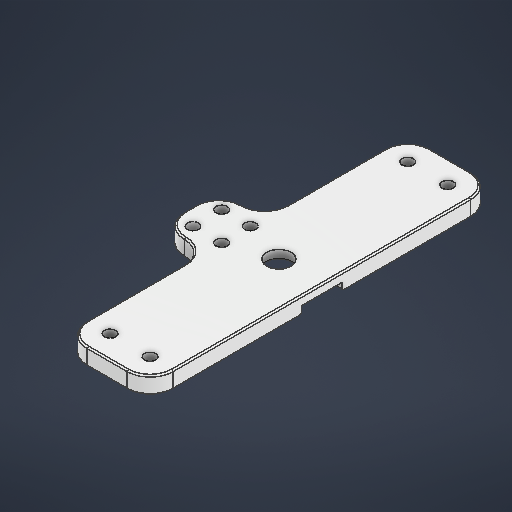
# Autodesk Inventor part: Cylinder fixing parts
Saved by Autodesk Inventor 2026.2 (Build 302298010, 298A)
## iProperties
Created: 2026-05-08
Part Number: Cylinder fixing parts
Material: ABS 플라스틱
Document SubType Name: Modeling
Designer: work
Density: 1.06 g/cm^3
Appearance: 매끄러움 - 흰색
Author: work
Autodesk Inventor part; units mm, degrees
ref_plane "YZ Plane" through (0, 0, 0) normal (1, 0, 0) x (0, 1, 0)
ref_plane "XZ Plane" through (0, 0, 0) normal (0, 1, 0) x (-1, 0, 0)
ref_plane "XY Plane" through (0, 0, 0) normal (0, 0, 1) x (1, 0, 0)
sketch "스케치1" plane through (0, 0, 0) normal (0, 1, 0) x (-1, 0, 0)
  circle A0 centre (0, 0) radius 4.25
  line L0 (-15, 60) -> (15, 60)
  line L1 (15, 60) -> (15, -60)
  line L2 (15, -60) -> (-15, -60)
  line L3 (-15, -60) -> (-15, 60)
  line L4 (-15, 60) -> (15, -60) construction
  line L5 (15, 60) -> (-15, -60) construction
  line L6 (-7, 52) -> (7, 52) construction
  line L7 (7, 52) -> (7, -52) construction
  line L8 (7, -52) -> (-7, -52) construction
  line L9 (-7, -52) -> (-7, 52) construction
  line L10 (-7, 52) -> (7, -52) construction
  line L11 (7, 52) -> (-7, -52) construction
  circle A1 centre (7, -52) radius 2
  circle A2 centre (-7, -52) radius 2
  circle A3 centre (7, 52) radius 2
  circle A4 centre (-7, 52) radius 2
  line L12 (31, -10) -> (0, -10)
  line L13 (0, -10) -> (0, 10) construction
  line L14 (0, 10) -> (31, 10)
  line L15 (31, 10) -> (31, -10)
  line L16 (25, 5) -> (25, -5) construction
  line L17 (31, 0) -> (0, 0) construction
  circle A5 centre (25, 5) radius 2
  circle A6 centre (25, -5) radius 2
  line L18 (25, 5) -> (15, 5) construction
  line L19 (15, 5) -> (15, -5) construction
  line L20 (15, -5) -> (25, -5) construction
  line L21 (25, -5) -> (25, 5) construction
  circle A7 centre (15, 5) radius 2
  circle A8 centre (15, -5) radius 2
  point P0 (25, 0)
  point P1 (15, -10)
  point P2 (15, 10)
  dimension "d0" = 8.5
  dimension "d1" = 120
  dimension "d2" = 30
  dimension "d3" = 8
  dimension "d4" = 4
  dimension "d5" = 4
  dimension "d6" = 4
  dimension "d7" = 4
  dimension "d8" = 8
  dimension "d9" = 16
  dimension "d10" = 20
  dimension "d11" = 6
  dimension "d13" = 4
  dimension "d14" = 4
  dimension "d15" = 10
  dimension "d16" = 4
  dimension "d17" = 4
  dimension "d18" = 10
  constraints: 44 end point, 9 centre point, 9 coincident, 8 parallel, 7 midpoint, 5 horizontal, 4 perpendicular, 1 point on line, 1 vertical
  measures "d0" diameter of A0
  measures "d1" distance of L0.end L1.end
  measures "d2" distance of L0.start L0.end
  measures "d3" distance between parallel lines of L0 L6
  measures "d4" diameter of A1
  measures "d5" diameter of A2
  measures "d6" diameter of A3
  measures "d7" diameter of A4
  measures "d8" distance between parallel lines of L1 L7
  measures "d9" distance between parallel lines of L1 L15
  measures "d10" distance of L14.end L12.start
  measures "d11" distance between parallel lines of L15 L16
  measures "d13" diameter of A5
  measures "d14" diameter of A6
  measures "d15" distance of L16.start L16.end
  measures "d16" diameter of A7
  measures "d17" diameter of A8
  measures "d18" distance between parallel lines of L21 L19
extrude "돌출1" add sketch "스케치1" along normal blind 6 contours L0 L1 A7 A8 L2 L3 | L14 L15 L12 L1 A8 A7
sketch "스케치2" plane through (0, 0, 0) normal (0, -1, 0) x (1, 0, 0)
  line L0 (30.1475, 7) -> (-8, 7)
  line L1 (-8, 7) -> (-8, -7)
  line L2 (-8, -7) -> (30.1475, -7)
  line L3 (30.1475, -7) -> (30.1475, 7)
  line L4 (-8, 0) -> (30.1475, 0) construction
  point P0 (0, 0)
  dimension "d21" = 8
  dimension "d22" = 14
  constraints: 10 end point, 2 midpoint, 2 parallel, 1 horizontal, 1 perpendicular, 1 point on line
  measures "d21" distance from line of L1 point (0, 0)
  measures "d22" distance between parallel lines of L2 L0
extrude "돌출2" cut sketch "스케치2" against normal blind 3
fillet "모깎기1" radius 8 8 edges at (-15, 3, 60) (15, 3, 60) (-15, 3, -60) (15, 3, -60) (-15, 3, -10) (-15, 3, 10) (-31, 3, 10) (-31, 3, -10)
chamfer "모따기1" distance 1 angle 45 3 edges at (-8, 0, 0) (3.5, 0, 7) (3.5, 0, -7)
chamfer "모따기2" distance 0.25 angle 45 1 edges at (4.25, 3, 0)
chamfer "모따기3" distance 0.5 angle 45 29 edges at (-15, 6, -35) (-23, 6, -10) (-28.657, 6, -7.657) (-31, 6, 0) (-28.657, 6, 7.657) (-23, 6, 10) (-15, 6, 35) (-12.657, 6, 57.657) (0, 6, 60) (12.657, 6, 57.657) (15, 6, 0) (12.657, 6, -57.657) (0, 6, -60) (-12.657, 6, -57.657) (-15, 0, -35) (-23, 0, -10) (-28.657, 0, -7.657) (-31, 0, 0) (-28.657, 0, 7.657) (-23, 0, 10) (-15, 0, 35) (-12.657, 0, 57.657) (0, 0, 60) (12.657, 0, 57.657) (15, 0, 30.0003) (-12.657, 0, -57.657) (0, 0, -60) (12.657, 0, -57.657) (15, 0, -30.0002)
